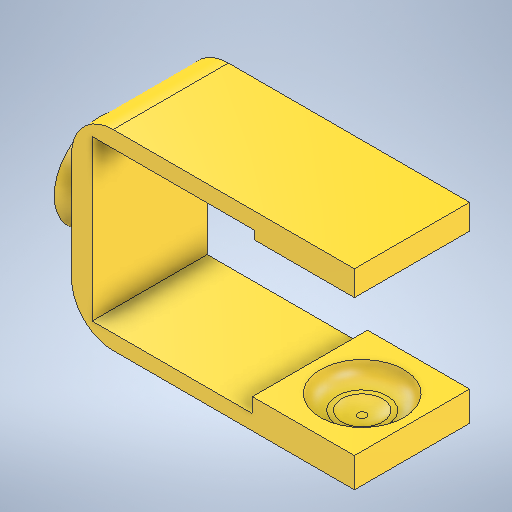
# Autodesk Inventor part: Penyangga fr
Saved by Autodesk Inventor 2025 (Build 290162000, 162)
## iProperties
Created: 2026-01-04
Part Number: Penyangga fr
Material: Generic
Document SubType Name: Modeling
Designer: novsa
Density: 1 g/cm^3
Appearance: Default
Mass: 2.64097 g
Surface Area: 31.4712 cm^2
Volume: 2.64097 cm^3
Author: novsa
Autodesk Inventor part; units mm, degrees
ref_plane "YZ Plane" through (0, 0, 0) normal (1, 0, 0) x (0, 1, 0)
ref_plane "XZ Plane" through (0, 0, 0) normal (0, 1, 0) x (-1, 0, 0)
ref_plane "XY Plane" through (0, 0, 0) normal (0, 0, 1) x (1, 0, 0)
sketch "Sketch1" plane through (0, 0, 0) normal (0, 1, 0) x (-1, 0, 0)
  line L0 (5.9835, 6.9145) -> (-5.9835, 6.9145)
  line L1 (-5.9835, 6.9145) -> (-5.9835, -6.9145)
  line L2 (-5.9835, -6.9145) -> (5.9835, -6.9145)
  line L3 (5.9835, -6.9145) -> (5.9835, 6.9145)
  line L4 (5.9835, 6.9145) -> (-5.9835, -6.9145) construction
  line L5 (-5.9835, 6.9145) -> (5.9835, -6.9145) construction
  point P0 (0, 0)
  dimension "d0" = 11.967
  dimension "d1" = 13.829
  constraints: 12 end point, 2 midpoint, 2 parallel, 1 horizontal, 1 perpendicular
  measures "d0" distance of L2.end L1.end
  measures "d1" distance of L0.end L1.end
extrude "Extrusion1" add sketch "Sketch1" along normal blind 3
sketch "Sketch2" plane through (0, 0, 0) normal (0, -1, 0) x (1, 0, 0)
  circle A0 centre (0, 0) radius 5.1
  dimension "d4" = 10.2
  constraints: 1 centre point, 1 coincident
  measures "d4" diameter of A0
extrude "Extrusion2" cut sketch "Sketch2" against normal blind 1.75
sketch "Sketch3" plane through (-5.9835, 0, -6.9145) normal (-1, 0, 0) x (0, 0, 1)
  line L0 (13.829, 3) -> (0, 3) projected
  line L1 (13.829, 0) -> (13.829, 3) projected
  line L2 (0, 3) -> (13.829, 3)
  line L3 (13.829, 3) -> (13.829, 1.014)
  line L4 (13.829, 1.014) -> (0, 1.014)
  line L5 (0, 1.014) -> (0, 3)
  point P0 (6.9145, 0)
  constraints: 8 end point, 2 parallel, 1 horizontal, 1 perpendicular, 1 point on line
extrude "Extrusion3" add sketch "Sketch3" along normal blind 22
sketch "Sketch4" plane through (-5.9835, 1.014, -6.9145) normal (0, -1, 0) x (1, 0, 0)
  line L0 (11.967, 0) -> (-22, 0) projected
  line L1 (11.967, 13.829) -> (-22, 13.829) projected
  line L2 (-22, 0) -> (-19.5337, 0)
  line L3 (-19.5337, 0) -> (-19.5337, 13.829)
  line L4 (-19.5337, 13.829) -> (-22, 13.829)
  line L5 (-22, 13.829) -> (-22, 0)
  point P0 (5.9835, 6.9145)
  constraints: 8 end point, 2 parallel, 1 horizontal, 1 perpendicular, 1 point on line
extrude "Extrusion4" add sketch "Sketch4" along normal blind 21
sketch "Sketch9" plane through (-25.5172, 1.014, 6.9145) normal (1, 0, 0) x (0, 0, -1)
  line L0 (0, 0) -> (0, -21) projected
  line L1 (13.829, 0) -> (13.829, -21) projected
  line L2 (0, -21) -> (13.829, -21)
  line L3 (13.829, -21) -> (13.829, -19.1968)
  line L4 (13.829, -19.1968) -> (0, -19.1968)
  line L5 (0, -19.1968) -> (0, -21)
  point P0 (6.9145, -1.014)
  point P1 (0, -19.1968)
  constraints: 8 end point, 2 parallel, 1 horizontal, 1 perpendicular, 1 point on line
extrude "Extrusion9" add sketch "Sketch9" along normal blind 19.25
sketch "Sketch10" plane through (-6.2672, 1.014, 6.9145) normal (1, 0, 0) x (0, 0, -1)
  line L0 (0, -21) -> (13.829, -21) projected
  line L1 (13.829, 1.986) -> (13.829, -21) projected
  line L2 (0, -21) -> (13.829, -21)
  line L3 (13.829, -21) -> (13.829, -17.4342)
  line L4 (13.829, -17.4342) -> (0, -17.4342)
  line L5 (0, -17.4342) -> (0, -21)
  point P0 (6.9145, -1.014)
  constraints: 8 end point, 2 parallel, 1 horizontal, 1 perpendicular, 1 point on line
extrude "Extrusion10" add sketch "Sketch10" along normal blind 12.25
sketch "Sketch11" plane through (-6.2672, -16.4202, 6.9145) normal (0, 1, 0) x (1, 0, 0)
  circle A0 centre (6.2672, 6.9145) radius 4.1 projected
  circle A1 centre (6.2672, 6.9145) radius 4.1
  constraints: 1 centre point, 1 coincident
extrude "Extrusion11" cut sketch "Sketch11" against normal blind 2.25
fillet "Fillet4" radius 4 1 edges at (-4.1, -18.6702, 0)
sketch "Sketch12" plane through (-27.9835, 0, -6.9145) normal (-1, 0, 0) x (0, 0, 1)
  circle A0 centre (6.9145, -8.8491) radius 5.5
  circle A1 centre (6.9145, -8.8491) radius 4.5533
  point P0 (6.9145, 0)
  dimension "d33" = 11
  constraints: 2 centre point
  measures "d33" diameter of A0
extrude "Extrusion12" add sketch "Sketch12" along normal blind 3.5
fillet "Fillet5" radius 5 2 edges at (-27.9835, 3, 0) (-27.9835, -19.986, 0)
sketch "Sketch13" plane through (-6.2672, -16.4202, 6.9145) normal (0, 1, 0) x (1, 0, 0)
  circle A0 centre (6.2672, 6.9145) radius 0.5031 projected
  circle A1 centre (6.2672, 6.9145) radius 5
  dimension "d37" = 10
  constraints: 1 centre point, 1 coincident
  measures "d37" diameter of A1
extrude "Extrusion13" cut sketch "Sketch13" against normal blind 1.75
fillet "Fillet6" radius 2 2 edges at (-5.1, 1.75, 0) (-5, -18.1702, 0)
body "Solid1"
